Autodesk Inventor part; units mm, degrees
(part 2 of 2)
  spline S54 degree 4 poles (-14.1067, -24.3314) (-14.1229, -24.3628) (-14.1546, -24.4254) (-14.1992, -24.5181) (-14.2532, -24.6396) (-14.3019, -24.7593) (-14.3455, -24.8773) (-14.3847, -24.9943) (-14.4205, -25.111) (-14.4537, -25.2282) (-14.4852, -25.3466) (-14.5154, -25.4664) (-14.5442, -25.5876) (-14.5715, -25.7098) (-14.5972, -25.8326) (-14.621, -25.9559) (-14.6431, -26.0796) (-14.6637, -26.2039) (-14.6827, -26.3288) (-14.7005, -26.4543) (-14.7169, -26.5805) (-14.7319, -26.7073) (-14.7456, -26.8346) (-14.758, -26.9623) (-14.769, -27.0904) (-14.7787, -27.219) (-14.7871, -27.348) (-14.7943, -27.4775) (-14.8002, -27.6074) (-14.8038, -27.7051) (-14.8058, -27.7704) (-14.8066, -27.8031) knots 0 0 0 0 0 0.035714 0.071429 0.107143 0.142857 0.178571 0.214286 0.25 0.285714 0.321429 0.357143 0.392857 0.428571 0.464286 0.5 0.535714 0.571429 0.607143 0.642857 0.678571 0.714286 0.75 0.785714 0.821429 0.857143 0.892857 0.928571 0.964286 1 1 1 1 1
  spline S55 degree 4 poles (-13.7901, -28.3211) (-13.7641, -28.3012) (-13.7125, -28.2612) (-13.6355, -28.2008) (-13.5339, -28.1196) (-13.4334, -28.0377) (-13.334, -27.9551) (-13.2357, -27.8717) (-13.1385, -27.7874) (-13.0424, -27.7024) (-12.9475, -27.6164) (-12.8538, -27.5297) (-12.7614, -27.4423) (-12.6702, -27.3541) (-12.5804, -27.2653) (-12.4919, -27.1757) (-12.4048, -27.0851) (-12.3191, -26.9933) (-12.2348, -26.9004) (-12.152, -26.8064) (-12.071, -26.7119) (-11.9917, -26.617) (-11.9144, -26.522) (-11.8391, -26.4262) (-11.7657, -26.3287) (-11.6941, -26.2282) (-11.6243, -26.1235) (-11.5561, -26.0139) (-11.4895, -25.8987) (-11.4407, -25.8081) (-11.4087, -25.7458) (-11.3928, -25.7142) knots 0 0 0 0 0 0.035714 0.071429 0.107143 0.142857 0.178571 0.214286 0.25 0.285714 0.321429 0.357143 0.392857 0.428571 0.464286 0.5 0.535714 0.571429 0.607143 0.642857 0.678571 0.714286 0.75 0.785714 0.821429 0.857143 0.892857 0.928571 0.964286 1 1 1 1 1
  spline S56 degree 4 poles (-10.1267, -26.2386) (-10.1379, -26.2722) (-10.1593, -26.339) (-10.1888, -26.4376) (-10.2231, -26.5662) (-10.2524, -26.6921) (-10.2771, -26.8155) (-10.2976, -26.9372) (-10.3147, -27.058) (-10.3292, -27.179) (-10.3417, -27.3008) (-10.3528, -27.4239) (-10.3623, -27.5481) (-10.3702, -27.6731) (-10.3763, -27.7984) (-10.3806, -27.9239) (-10.3831, -28.0495) (-10.3839, -28.1755) (-10.3832, -28.3018) (-10.3811, -28.4285) (-10.3775, -28.5557) (-10.3726, -28.6833) (-10.3662, -28.8111) (-10.3584, -28.9392) (-10.3493, -29.0675) (-10.3387, -29.1959) (-10.3269, -29.3247) (-10.3137, -29.4536) (-10.2993, -29.5828) (-10.2875, -29.6799) (-10.2792, -29.7447) (-10.275, -29.7771) knots 0 0 0 0 0 0.035714 0.071429 0.107143 0.142857 0.178571 0.214286 0.25 0.285714 0.321429 0.357143 0.392857 0.428571 0.464286 0.5 0.535714 0.571429 0.607143 0.642857 0.678571 0.714286 0.75 0.785714 0.821429 0.857143 0.892857 0.928571 0.964286 1 1 1 1 1
  spline S57 degree 4 poles (-9.1899, -30.1297) (-9.1674, -30.1059) (-9.1226, -30.0582) (-9.056, -29.9865) (-8.9684, -29.8904) (-8.8819, -29.7937) (-8.7967, -29.6964) (-8.7126, -29.5985) (-8.6298, -29.5001) (-8.5482, -29.4009) (-8.4679, -29.3012) (-8.3889, -29.2008) (-8.3113, -29.0999) (-8.235, -28.9986) (-8.1602, -28.8968) (-8.0869, -28.7944) (-8.015, -28.6913) (-7.9447, -28.5872) (-7.876, -28.4822) (-7.8089, -28.3765) (-7.7436, -28.2705) (-7.6802, -28.1645) (-7.6187, -28.0586) (-7.5593, -27.9523) (-7.502, -27.8446) (-7.4471, -27.7342) (-7.3945, -27.62) (-7.3443, -27.5012) (-7.2965, -27.3771) (-7.2625, -27.2801) (-7.2407, -27.2135) (-7.23, -27.1798) knots 0 0 0 0 0 0.035714 0.071429 0.107143 0.142857 0.178571 0.214286 0.25 0.285714 0.321429 0.357143 0.392857 0.428571 0.464286 0.5 0.535714 0.571429 0.607143 0.642857 0.678571 0.714286 0.75 0.785714 0.821429 0.857143 0.892857 0.928571 0.964286 1 1 1 1 1
  spline S58 degree 4 poles (-5.8974, -27.4997) (-5.9032, -27.5347) (-5.9139, -27.6039) (-5.9277, -27.7059) (-5.9415, -27.8381) (-5.9508, -27.9669) (-5.9558, -28.0927) (-5.957, -28.216) (-5.955, -28.338) (-5.9503, -28.4598) (-5.9437, -28.5821) (-5.9353, -28.7054) (-5.9253, -28.8295) (-5.9135, -28.9542) (-5.9, -29.0789) (-5.8846, -29.2036) (-5.8674, -29.3281) (-5.8485, -29.4526) (-5.828, -29.5772) (-5.8061, -29.7021) (-5.7827, -29.8272) (-5.7579, -29.9524) (-5.7316, -30.0777) (-5.7038, -30.203) (-5.6747, -30.3283) (-5.6442, -30.4536) (-5.6123, -30.5789) (-5.5792, -30.7043) (-5.5447, -30.8297) (-5.5179, -30.9237) (-5.4996, -30.9865) (-5.4903, -31.0178) knots 0 0 0 0 0 0.035714 0.071429 0.107143 0.142857 0.178571 0.214286 0.25 0.285714 0.321429 0.357143 0.392857 0.428571 0.464286 0.5 0.535714 0.571429 0.607143 0.642857 0.678571 0.714286 0.75 0.785714 0.821429 0.857143 0.892857 0.928571 0.964286 1 1 1 1 1
  spline S59 degree 4 poles (-4.3634, -31.1963) (-4.345, -31.1693) (-4.3082, -31.1153) (-4.2537, -31.0341) (-4.1822, -30.9254) (-4.112, -30.8164) (-4.0431, -30.707) (-3.9754, -30.5972) (-3.909, -30.487) (-3.844, -30.3764) (-3.7803, -30.2653) (-3.7181, -30.1538) (-3.6572, -30.0421) (-3.5978, -29.93) (-3.5398, -29.8178) (-3.4834, -29.7052) (-3.4286, -29.5921) (-3.3754, -29.4783) (-3.3239, -29.3639) (-3.2742, -29.249) (-3.2263, -29.134) (-3.1802, -29.0194) (-3.136, -28.9051) (-3.094, -28.7908) (-3.0542, -28.6754) (-3.0172, -28.5578) (-2.983, -28.4367) (-2.9519, -28.3114) (-2.9241, -28.1814) (-2.9057, -28.0803) (-2.8944, -28.0112) (-2.8891, -27.9762) knots 0 0 0 0 0 0.035714 0.071429 0.107143 0.142857 0.178571 0.214286 0.25 0.285714 0.321429 0.357143 0.392857 0.428571 0.464286 0.5 0.535714 0.571429 0.607143 0.642857 0.678571 0.714286 0.75 0.785714 0.821429 0.857143 0.892857 0.928571 0.964286 1 1 1 1 1
  spline S60 degree 4 poles (-1.5229, -28.0837) (-1.5231, -28.1192) (-1.5229, -28.1892) (-1.5205, -28.2922) (-1.5134, -28.4251) (-1.5024, -28.5538) (-1.4877, -28.6788) (-1.4696, -28.8008) (-1.4485, -28.921) (-1.4249, -29.0406) (-1.3992, -29.1603) (-1.3717, -29.2808) (-1.3424, -29.4019) (-1.3113, -29.5231) (-1.2784, -29.6442) (-1.2436, -29.7649) (-1.2072, -29.8852) (-1.169, -30.0052) (-1.1293, -30.1251) (-1.0881, -30.245) (-1.0455, -30.3649) (-1.0014, -30.4847) (-0.9558, -30.6043) (-0.9088, -30.7237) (-0.8604, -30.8429) (-0.8107, -30.9618) (-0.7596, -31.0806) (-0.7073, -31.1991) (-0.6536, -31.3175) (-0.6124, -31.4062) (-0.5845, -31.4653) (-0.5705, -31.4948) knots 0 0 0 0 0 0.035714 0.071429 0.107143 0.142857 0.178571 0.214286 0.25 0.285714 0.321429 0.357143 0.392857 0.428571 0.464286 0.5 0.535714 0.571429 0.607143 0.642857 0.678571 0.714286 0.75 0.785714 0.821429 0.857143 0.892857 0.928571 0.964286 1 1 1 1 1
  spline S61 degree 4 poles (0.5705, -31.4948) (0.5845, -31.4653) (0.6124, -31.4062) (0.6536, -31.3174) (0.7072, -31.1989) (0.7595, -31.0803) (0.8106, -30.9615) (0.8603, -30.8425) (0.9087, -30.7233) (0.9556, -30.6038) (1.0012, -30.4842) (1.0453, -30.3644) (1.0879, -30.2444) (1.1291, -30.1245) (1.1688, -30.0046) (1.2069, -29.8846) (1.2434, -29.7643) (1.2781, -29.6436) (1.3111, -29.5225) (1.3422, -29.4012) (1.3715, -29.2802) (1.3991, -29.1597) (1.4248, -29.04) (1.4484, -28.9205) (1.4696, -28.8003) (1.4877, -28.6783) (1.5025, -28.5534) (1.5135, -28.4248) (1.5206, -28.292) (1.5229, -28.1891) (1.5231, -28.1191) (1.5229, -28.0837) knots 0 0 0 0 0 0.035714 0.071429 0.107143 0.142857 0.178571 0.214286 0.25 0.285714 0.321429 0.357143 0.392857 0.428571 0.464286 0.5 0.535714 0.571429 0.607143 0.642857 0.678571 0.714286 0.75 0.785714 0.821429 0.857143 0.892857 0.928571 0.964286 1 1 1 1 1
  spline S62 degree 4 poles (2.8891, -27.9762) (2.8944, -28.0112) (2.9056, -28.0804) (2.924, -28.1816) (2.9518, -28.3117) (2.9827, -28.4371) (3.0168, -28.5582) (3.0538, -28.676) (3.0935, -28.7914) (3.1355, -28.9058) (3.1796, -29.0201) (3.2257, -29.1348) (3.2736, -29.2498) (3.3233, -29.3647) (3.3747, -29.4792) (3.4279, -29.5929) (3.4827, -29.706) (3.5392, -29.8186) (3.5971, -29.9308) (3.6566, -30.0428) (3.7175, -30.1545) (3.7798, -30.266) (3.8435, -30.377) (3.9086, -30.4876) (3.975, -30.5977) (4.0428, -30.7074) (4.1118, -30.8167) (4.182, -30.9256) (4.2536, -31.0342) (4.3081, -31.1154) (4.3449, -31.1694) (4.3634, -31.1963) knots 0 0 0 0 0 0.035714 0.071429 0.107143 0.142857 0.178571 0.214286 0.25 0.285714 0.321429 0.357143 0.392857 0.428571 0.464286 0.5 0.535714 0.571429 0.607143 0.642857 0.678571 0.714286 0.75 0.785714 0.821429 0.857143 0.892857 0.928571 0.964286 1 1 1 1 1
  spline S63 degree 4 poles (5.4903, -31.0178) (5.4996, -30.9865) (5.5179, -30.9237) (5.5447, -30.8297) (5.5791, -30.7043) (5.6123, -30.579) (5.6441, -30.4537) (5.6746, -30.3284) (5.7038, -30.2031) (5.7315, -30.0778) (5.7577, -29.9525) (5.7826, -29.8273) (5.806, -29.7022) (5.8279, -29.5773) (5.8483, -29.4526) (5.8672, -29.3281) (5.8844, -29.2036) (5.8998, -29.079) (5.9134, -28.9543) (5.9251, -28.8296) (5.9352, -28.7055) (5.9436, -28.5822) (5.9502, -28.4598) (5.9549, -28.3381) (5.9569, -28.216) (5.9558, -28.0926) (5.9508, -27.9669) (5.9415, -27.8381) (5.9277, -27.7058) (5.9139, -27.6039) (5.9032, -27.5347) (5.8974, -27.4997) knots 0 0 0 0 0 0.035714 0.071429 0.107143 0.142857 0.178571 0.214286 0.25 0.285714 0.321429 0.357143 0.392857 0.428571 0.464286 0.5 0.535714 0.571429 0.607143 0.642857 0.678571 0.714286 0.75 0.785714 0.821429 0.857143 0.892857 0.928571 0.964286 1 1 1 1 1
  spline S64 degree 4 poles (7.23, -27.1798) (7.2407, -27.2136) (7.2626, -27.2801) (7.2966, -27.3773) (7.3443, -27.5014) (7.3945, -27.6204) (7.4471, -27.7347) (7.5021, -27.8452) (7.5593, -27.953) (7.6187, -28.0594) (7.6802, -28.1654) (7.7436, -28.2714) (7.8089, -28.3775) (7.876, -28.4832) (7.9447, -28.5882) (8.015, -28.6923) (8.0869, -28.7954) (8.1602, -28.8977) (8.235, -28.9995) (8.3113, -29.1008) (8.3889, -29.2017) (8.4679, -29.302) (8.5482, -29.4017) (8.6298, -29.5007) (8.7126, -29.5991) (8.7967, -29.6969) (8.8819, -29.794) (8.9684, -29.8906) (9.056, -29.9867) (9.1226, -30.0583) (9.1674, -30.1059) (9.1899, -30.1297) knots 0 0 0 0 0 0.035714 0.071429 0.107143 0.142857 0.178571 0.214286 0.25 0.285714 0.321429 0.357143 0.392857 0.428571 0.464286 0.5 0.535714 0.571429 0.607143 0.642857 0.678571 0.714286 0.75 0.785714 0.821429 0.857143 0.892857 0.928571 0.964286 1 1 1 1 1
  spline S65 degree 4 poles (10.275, -29.7771) (10.2792, -29.7446) (10.2874, -29.6798) (10.2992, -29.5826) (10.3135, -29.4533) (10.3266, -29.3243) (10.3384, -29.1955) (10.3489, -29.0669) (10.3581, -28.9386) (10.3658, -28.8104) (10.3721, -28.6825) (10.377, -28.5549) (10.3805, -28.4277) (10.3826, -28.3009) (10.3833, -28.1745) (10.3825, -28.0486) (10.38, -27.9229) (10.3758, -27.7974) (10.3696, -27.6721) (10.3618, -27.5471) (10.3523, -27.423) (10.3413, -27.2999) (10.3288, -27.1781) (10.3144, -27.0572) (10.2973, -26.9364) (10.277, -26.8148) (10.2524, -26.6915) (10.2231, -26.5658) (10.1889, -26.4374) (10.1593, -26.3389) (10.1379, -26.2722) (10.1267, -26.2386) knots 0 0 0 0 0 0.035714 0.071429 0.107143 0.142857 0.178571 0.214286 0.25 0.285714 0.321429 0.357143 0.392857 0.428571 0.464286 0.5 0.535714 0.571429 0.607143 0.642857 0.678571 0.714286 0.75 0.785714 0.821429 0.857143 0.892857 0.928571 0.964286 1 1 1 1 1
  spline S66 degree 4 poles (11.3928, -25.7142) (11.4087, -25.7458) (11.4407, -25.8081) (11.4895, -25.8987) (11.5561, -26.0139) (11.6243, -26.1236) (11.6941, -26.2283) (11.7657, -26.3288) (11.8391, -26.4263) (11.9144, -26.5221) (11.9917, -26.6172) (12.071, -26.712) (12.152, -26.8066) (12.2348, -26.9005) (12.3191, -26.9935) (12.4048, -27.0852) (12.4919, -27.1759) (12.5804, -27.2655) (12.6702, -27.3543) (12.7614, -27.4424) (12.8538, -27.5299) (12.9475, -27.6166) (13.0424, -27.7025) (13.1385, -27.7875) (13.2357, -27.8718) (13.334, -27.9552) (13.4334, -28.0378) (13.5339, -28.1197) (13.6355, -28.2009) (13.7125, -28.2612) (13.7641, -28.3012) (13.7901, -28.3211) knots 0 0 0 0 0 0.035714 0.071429 0.107143 0.142857 0.178571 0.214286 0.25 0.285714 0.321429 0.357143 0.392857 0.428571 0.464286 0.5 0.535714 0.571429 0.607143 0.642857 0.678571 0.714286 0.75 0.785714 0.821429 0.857143 0.892857 0.928571 0.964286 1 1 1 1 1
  spline S67 degree 4 poles (14.8066, -27.8031) (14.8058, -27.7704) (14.8038, -27.7051) (14.8002, -27.6074) (14.7942, -27.4775) (14.7871, -27.348) (14.7786, -27.219) (14.7689, -27.0905) (14.7579, -26.9623) (14.7456, -26.8346) (14.7319, -26.7073) (14.7168, -26.5806) (14.7004, -26.4544) (14.6826, -26.3288) (14.6635, -26.204) (14.643, -26.0797) (14.6209, -25.956) (14.5971, -25.8327) (14.5714, -25.7099) (14.5441, -25.5877) (14.5152, -25.4665) (14.4851, -25.3466) (14.4536, -25.2282) (14.4204, -25.111) (14.3847, -24.9943) (14.3454, -24.8773) (14.3018, -24.7593) (14.2532, -24.6396) (14.1992, -24.5181) (14.1545, -24.4253) (14.1229, -24.3628) (14.1067, -24.3314) knots 0 0 0 0 0 0.035714 0.071429 0.107143 0.142857 0.178571 0.214286 0.25 0.285714 0.321429 0.357143 0.392857 0.428571 0.464286 0.5 0.535714 0.571429 0.607143 0.642857 0.678571 0.714286 0.75 0.785714 0.821429 0.857143 0.892857 0.928571 0.964286 1 1 1 1 1
  spline S68 degree 4 poles (15.2751, -23.6154) (15.2958, -23.6441) (15.3371, -23.7007) (15.3995, -23.7826) (15.4833, -23.8859) (15.5678, -23.9835) (15.6532, -24.076) (15.7396, -24.1641) (15.8273, -24.249) (15.9167, -24.3318) (16.0079, -24.4136) (16.101, -24.4949) (16.1959, -24.5756) (16.2924, -24.6554) (16.3902, -24.734) (16.4892, -24.8113) (16.5894, -24.8871) (16.6908, -24.9618) (16.7934, -25.0355) (16.8972, -25.1083) (17.0022, -25.1802) (17.1083, -25.2512) (17.2155, -25.3212) (17.3236, -25.3901) (17.4328, -25.4581) (17.543, -25.5251) (17.6541, -25.5912) (17.7662, -25.6563) (17.8792, -25.7206) (17.9647, -25.7681) (18.022, -25.7995) (18.0507, -25.8152) knots 0 0 0 0 0 0.035714 0.071429 0.107143 0.142857 0.178571 0.214286 0.25 0.285714 0.321429 0.357143 0.392857 0.428571 0.464286 0.5 0.535714 0.571429 0.607143 0.642857 0.678571 0.714286 0.75 0.785714 0.821429 0.857143 0.892857 0.928571 0.964286 1 1 1 1 1
  spline S69 degree 4 poles (18.9737, -25.1445) (18.9677, -25.1124) (18.9555, -25.0482) (18.9367, -24.9522) (18.9105, -24.8248) (18.8831, -24.6981) (18.8546, -24.572) (18.8249, -24.4465) (18.794, -24.3217) (18.7618, -24.1975) (18.7283, -24.0739) (18.6936, -23.951) (18.6576, -23.829) (18.6205, -23.7077) (18.5821, -23.5874) (18.5424, -23.4679) (18.5012, -23.3491) (18.4584, -23.2311) (18.4138, -23.1138) (18.3677, -22.9974) (18.3203, -22.8822) (18.2718, -22.7685) (18.2222, -22.6565) (18.171, -22.5459) (18.1175, -22.4362) (18.0604, -22.3269) (17.9989, -22.2171) (17.9321, -22.1066) (17.8598, -21.995) (17.8012, -21.9104) (17.7602, -21.8536) (17.7393, -21.8251) knots 0 0 0 0 0 0.035714 0.071429 0.107143 0.142857 0.178571 0.214286 0.25 0.285714 0.321429 0.357143 0.392857 0.428571 0.464286 0.5 0.535714 0.571429 0.607143 0.642857 0.678571 0.714286 0.75 0.785714 0.821429 0.857143 0.892857 0.928571 0.964286 1 1 1 1 1
  spline S70 degree 4 poles (18.7813, -20.9351) (18.8062, -20.9602) (18.8559, -21.0096) (18.9303, -21.0807) (19.0292, -21.1696) (19.1279, -21.2528) (19.2266, -21.3307) (19.3257, -21.4041) (19.4256, -21.4741) (19.5268, -21.5419) (19.6297, -21.6084) (19.7343, -21.674) (19.8407, -21.7389) (19.9484, -21.8026) (20.0573, -21.865) (20.1672, -21.9258) (20.278, -21.985) (20.3899, -22.0429) (20.5027, -22.0997) (20.6167, -22.1554) (20.7316, -22.21) (20.8476, -22.2635) (20.9644, -22.3159) (21.0821, -22.3672) (21.2006, -22.4173) (21.3199, -22.4663) (21.44, -22.5142) (21.5609, -22.5611) (21.6826, -22.6069) (21.7745, -22.6406) (21.836, -22.6626) (21.8668, -22.6736) knots 0 0 0 0 0 0.035714 0.071429 0.107143 0.142857 0.178571 0.214286 0.25 0.285714 0.321429 0.357143 0.392857 0.428571 0.464286 0.5 0.535714 0.571429 0.607143 0.642857 0.678571 0.714286 0.75 0.785714 0.821429 0.857143 0.892857 0.928571 0.964286 1 1 1 1 1
  spline S71 degree 4 poles (22.6736, -21.8668) (22.6626, -21.836) (22.6406, -21.7745) (22.607, -21.6827) (22.5612, -21.561) (22.5143, -21.4401) (22.4665, -21.32) (22.4175, -21.2007) (22.3674, -21.0823) (22.3162, -20.9646) (22.2638, -20.8478) (22.2103, -20.7319) (22.1557, -20.617) (22.1001, -20.5031) (22.0433, -20.3902) (21.9854, -20.2784) (21.9262, -20.1675) (21.8654, -20.0576) (21.803, -19.9487) (21.7393, -19.841) (21.6744, -19.7347) (21.6087, -19.63) (21.5422, -19.5271) (21.4743, -19.4258) (21.4043, -19.3259) (21.3308, -19.2268) (21.2528, -19.128) (21.1696, -19.0292) (21.0807, -18.9303) (21.0096, -18.8559) (20.9602, -18.8062) (20.9351, -18.7813) knots 0 0 0 0 0 0.035714 0.071429 0.107143 0.142857 0.178571 0.214286 0.25 0.285714 0.321429 0.357143 0.392857 0.428571 0.464286 0.5 0.535714 0.571429 0.607143 0.642857 0.678571 0.714286 0.75 0.785714 0.821429 0.857143 0.892857 0.928571 0.964286 1 1 1 1 1
  spline S72 degree 4 poles (21.8251, -17.7393) (21.8536, -17.7602) (21.9104, -17.8012) (21.995, -17.8598) (22.1066, -17.9322) (22.2172, -17.9989) (22.327, -18.0605) (22.4364, -18.1175) (22.546, -18.1711) (22.6567, -18.2223) (22.7687, -18.2719) (22.8824, -18.3204) (22.9975, -18.3679) (23.1139, -18.414) (23.2312, -18.4586) (23.3493, -18.5014) (23.468, -18.5426) (23.5875, -18.5823) (23.7079, -18.6206) (23.8291, -18.6578) (23.9512, -18.6938) (24.074, -18.7285) (24.1976, -18.7619) (24.3218, -18.7941) (24.4466, -18.825) (24.5721, -18.8547) (24.6982, -18.8832) (24.8249, -18.9105) (24.9522, -18.9368) (25.0482, -18.9556) (25.1124, -18.9677) (25.1445, -18.9737) knots 0 0 0 0 0 0.035714 0.071429 0.107143 0.142857 0.178571 0.214286 0.25 0.285714 0.321429 0.357143 0.392857 0.428571 0.464286 0.5 0.535714 0.571429 0.607143 0.642857 0.678571 0.714286 0.75 0.785714 0.821429 0.857143 0.892857 0.928571 0.964286 1 1 1 1 1
  spline S73 degree 4 poles (25.8152, -18.0507) (25.7995, -18.022) (25.7681, -17.9647) (25.7206, -17.8792) (25.6563, -17.7662) (25.5911, -17.6541) (25.525, -17.543) (25.458, -17.4328) (25.39, -17.3236) (25.321, -17.2155) (25.251, -17.1083) (25.18, -17.0022) (25.1081, -16.8972) (25.0353, -16.7934) (24.9616, -16.6908) (24.8869, -16.5894) (24.8111, -16.4892) (24.7338, -16.3902) (24.6552, -16.2923) (24.5754, -16.1959) (24.4947, -16.101) (24.4134, -16.0079) (24.3316, -15.9167) (24.2488, -15.8273) (24.164, -15.7395) (24.0759, -15.6531) (23.9834, -15.5678) (23.8858, -15.4833) (23.7825, -15.3995) (23.7007, -15.3371) (23.6441, -15.2958) (23.6154, -15.2751) knots 0 0 0 0 0 0.035714 0.071429 0.107143 0.142857 0.178571 0.214286 0.25 0.285714 0.321429 0.357143 0.392857 0.428571 0.464286 0.5 0.535714 0.571429 0.607143 0.642857 0.678571 0.714286 0.75 0.785714 0.821429 0.857143 0.892857 0.928571 0.964286 1 1 1 1 1
  spline S74 degree 4 poles (24.3314, -14.1067) (24.3628, -14.1229) (24.4253, -14.1545) (24.5181, -14.1991) (24.6396, -14.2531) (24.7593, -14.3017) (24.8773, -14.3454) (24.9943, -14.3846) (25.111, -14.4203) (25.2282, -14.4536) (25.3466, -14.485) (25.4665, -14.5152) (25.5877, -14.544) (25.7098, -14.5713) (25.8327, -14.597) (25.956, -14.6208) (26.0797, -14.6429) (26.2039, -14.6635) (26.3288, -14.6825) (26.4543, -14.7003) (26.5805, -14.7167) (26.7073, -14.7318) (26.8346, -14.7455) (26.9623, -14.7579) (27.0905, -14.7689) (27.219, -14.7786) (27.348, -14.787) (27.4775, -14.7942) (27.6074, -14.8002) (27.7051, -14.8038) (27.7704, -14.8058) (27.8031, -14.8066) knots 0 0 0 0 0 0.035714 0.071429 0.107143 0.142857 0.178571 0.214286 0.25 0.285714 0.321429 0.357143 0.392857 0.428571 0.464286 0.5 0.535714 0.571429 0.607143 0.642857 0.678571 0.714286 0.75 0.785714 0.821429 0.857143 0.892857 0.928571 0.964286 1 1 1 1 1
  spline S75 degree 4 poles (28.3211, -13.7901) (28.3012, -13.7641) (28.2612, -13.7125) (28.2008, -13.6355) (28.1196, -13.5339) (28.0377, -13.4334) (27.955, -13.334) (27.8716, -13.2357) (27.7874, -13.1385) (27.7023, -13.0424) (27.6164, -12.9475) (27.5296, -12.8538) (27.4422, -12.7613) (27.354, -12.6702) (27.2652, -12.5804) (27.1756, -12.4919) (27.085, -12.4048) (26.9932, -12.3191) (26.9003, -12.2348) (26.8063, -12.152) (26.7118, -12.0709) (26.617, -11.9917) (26.5219, -11.9144) (26.4261, -11.8391) (26.3286, -11.7657) (26.2281, -11.6941) (26.1235, -11.6243) (26.0138, -11.5561) (25.8987, -11.4895) (25.8081, -11.4407) (25.7458, -11.4087) (25.7142, -11.3928) knots 0 0 0 0 0 0.035714 0.071429 0.107143 0.142857 0.178571 0.214286 0.25 0.285714 0.321429 0.357143 0.392857 0.428571 0.464286 0.5 0.535714 0.571429 0.607143 0.642857 0.678571 0.714286 0.75 0.785714 0.821429 0.857143 0.892857 0.928571 0.964286 1 1 1 1 1
  spline S76 degree 4 poles (26.2386, -10.1267) (26.2722, -10.1379) (26.3389, -10.1593) (26.4375, -10.1889) (26.566, -10.2232) (26.6918, -10.2525) (26.8152, -10.2771) (26.9369, -10.2976) (27.0578, -10.3147) (27.1788, -10.3292) (27.3006, -10.3417) (27.4237, -10.3528) (27.5479, -10.3623) (27.6729, -10.3702) (27.7982, -10.3763) (27.9237, -10.3806) (28.0494, -10.3831) (28.1753, -10.3839) (28.3016, -10.3832) (28.4284, -10.3811) (28.5556, -10.3775) (28.6832, -10.3726) (28.811, -10.3662) (28.9391, -10.3584) (29.0674, -10.3493) (29.1959, -10.3387) (29.3246, -10.3268) (29.4536, -10.3137) (29.5828, -10.2993) (29.6798, -10.2875) (29.7447, -10.2792) (29.7771, -10.275) knots 0 0 0 0 0 0.035714 0.071429 0.107143 0.142857 0.178571 0.214286 0.25 0.285714 0.321429 0.357143 0.392857 0.428571 0.464286 0.5 0.535714 0.571429 0.607143 0.642857 0.678571 0.714286 0.75 0.785714 0.821429 0.857143 0.892857 0.928571 0.964286 1 1 1 1 1
  spline S77 degree 4 poles (30.1297, -9.1899) (30.1059, -9.1674) (30.0583, -9.1226) (29.9867, -9.056) (29.8906, -8.9684) (29.794, -8.882) (29.6968, -8.7968) (29.5991, -8.7127) (29.5007, -8.6299) (29.4016, -8.5483) (29.3019, -8.4681) (29.2016, -8.3891) (29.1008, -8.3115) (28.9995, -8.2353) (28.8977, -8.1604) (28.7953, -8.0871) (28.6922, -8.0152) (28.5881, -7.9449) (28.4832, -7.8762) (28.3774, -7.8092) (28.2713, -7.7439) (28.1653, -7.6804) (28.0593, -7.6189) (27.9529, -7.5595) (27.8451, -7.5022) (27.7346, -7.4473) (27.6203, -7.3946) (27.5013, -7.3444) (27.3772, -7.2966) (27.2801, -7.2626) (27.2135, -7.2407) (27.1798, -7.23) knots 0 0 0 0 0 0.035714 0.071429 0.107143 0.142857 0.178571 0.214286 0.25 0.285714 0.321429 0.357143 0.392857 0.428571 0.464286 0.5 0.535714 0.571429 0.607143 0.642857 0.678571 0.714286 0.75 0.785714 0.821429 0.857143 0.892857 0.928571 0.964286 1 1 1 1 1
  spline S78 degree 4 poles (27.4997, -5.8974) (27.5347, -5.9032) (27.6039, -5.9139) (27.7059, -5.9277) (27.8382, -5.9415) (27.967, -5.9508) (28.0928, -5.9558) (28.2161, -5.957) (28.3382, -5.955) (28.46, -5.9504) (28.5823, -5.9437) (28.7056, -5.9353) (28.8298, -5.9253) (28.9544, -5.9136) (29.0792, -5.9) (29.2038, -5.8846) (29.3283, -5.8674) (29.4528, -5.8485) (29.5775, -5.828) (29.7023, -5.8061) (29.8274, -5.7827) (29.9527, -5.7579) (30.0779, -5.7316) (30.2032, -5.7039) (30.3285, -5.6747) (30.4537, -5.6442) (30.579, -5.6124) (30.7043, -5.5792) (30.8297, -5.5447) (30.9238, -5.5179) (30.9865, -5.4996) (31.0178, -5.4903) knots 0 0 0 0 0 0.035714 0.071429 0.107143 0.142857 0.178571 0.214286 0.25 0.285714 0.321429 0.357143 0.392857 0.428571 0.464286 0.5 0.535714 0.571429 0.607143 0.642857 0.678571 0.714286 0.75 0.785714 0.821429 0.857143 0.892857 0.928571 0.964286 1 1 1 1 1
  spline S79 degree 4 poles (31.1963, -4.3634) (31.1694, -4.3449) (31.1153, -4.3081) (31.0342, -4.2536) (30.9256, -4.1821) (30.8166, -4.1118) (30.7073, -4.0428) (30.5976, -3.9751) (30.4874, -3.9087) (30.3769, -3.8436) (30.2658, -3.7799) (30.1544, -3.7176) (30.0427, -3.6567) (29.9307, -3.5973) (29.8184, -3.5393) (29.7059, -3.4829) (29.5928, -3.428) (29.479, -3.3749) (29.3645, -3.3234) (29.2496, -3.2737) (29.1346, -3.2258) (29.02, -3.1797) (28.9057, -3.1356) (28.7913, -3.0936) (28.6759, -3.0539) (28.5582, -3.0169) (28.437, -2.9828) (28.3117, -2.9518) (28.1816, -2.924) (28.0803, -2.9056) (28.0112, -2.8944) (27.9762, -2.8891) knots 0 0 0 0 0 0.035714 0.071429 0.107143 0.142857 0.178571 0.214286 0.25 0.285714 0.321429 0.357143 0.392857 0.428571 0.464286 0.5 0.535714 0.571429 0.607143 0.642857 0.678571 0.714286 0.75 0.785714 0.821429 0.857143 0.892857 0.928571 0.964286 1 1 1 1 1
  arc A0 (31.4948, -0.5705) -> (31.4948, 0.5705) centre (0, 0) ccw
  arc A1 (28.0837, 1.5229) -> (27.9762, 2.8891) centre (0, 0) ccw
  arc A2 (31.1963, 4.3634) -> (31.0178, 5.4903) centre (0, 0) ccw
  arc A3 (27.4997, 5.8974) -> (27.1798, 7.23) centre (0, 0) ccw
  arc A4 (30.1297, 9.1899) -> (29.7771, 10.275) centre (0, 0) ccw
  arc A5 (26.2386, 10.1267) -> (25.7142, 11.3928) centre (0, 0) ccw
  arc A6 (28.3211, 13.7901) -> (27.8031, 14.8066) centre (0, 0) ccw
  arc A7 (24.3314, 14.1067) -> (23.6154, 15.2751) centre (0, 0) ccw
  arc A8 (25.8152, 18.0507) -> (25.1445, 18.9737) centre (0, 0) ccw
  arc A9 (21.8251, 17.7393) -> (20.9351, 18.7813) centre (0, 0) ccw
  arc A10 (22.6736, 21.8668) -> (21.8668, 22.6736) centre (0, 0) ccw
  arc A11 (18.7813, 20.9351) -> (17.7393, 21.8251) centre (0, 0) ccw
  arc A12 (18.9737, 25.1445) -> (18.0507, 25.8152) centre (0, 0) ccw
  arc A13 (15.2751, 23.6154) -> (14.1067, 24.3314) centre (0, 0) ccw
  arc A14 (14.8066, 27.8031) -> (13.7901, 28.3211) centre (0, 0) ccw
  arc A15 (11.3928, 25.7142) -> (10.1267, 26.2386) centre (0, 0) ccw
  arc A16 (10.275, 29.7771) -> (9.1899, 30.1297) centre (0, 0) ccw
  arc A17 (7.23, 27.1798) -> (5.8974, 27.4997) centre (0, 0) ccw
  arc A18 (5.4903, 31.0178) -> (4.3634, 31.1963) centre (0, 0) ccw
  arc A19 (2.8891, 27.9762) -> (1.5229, 28.0837) centre (0, 0) ccw
  arc A20 (0.5705, 31.4948) -> (-0.5705, 31.4948) centre (0, 0) ccw
  arc A21 (-1.5229, 28.0837) -> (-2.8891, 27.9762) centre (0, 0) ccw
  arc A22 (-4.3634, 31.1963) -> (-5.4903, 31.0178) centre (0, 0) ccw
  arc A23 (-5.8974, 27.4997) -> (-7.23, 27.1798) centre (0, 0) ccw
  arc A24 (-9.1899, 30.1297) -> (-10.275, 29.7771) centre (0, 0) ccw
  arc A25 (-10.1267, 26.2386) -> (-11.3928, 25.7142) centre (0, 0) ccw
  arc A26 (-13.7901, 28.3211) -> (-14.8066, 27.8031) centre (0, 0) ccw
  arc A27 (-14.1067, 24.3314) -> (-15.2751, 23.6154) centre (0, 0) ccw
  arc A28 (-18.0507, 25.8152) -> (-18.9737, 25.1445) centre (0, 0) ccw
  arc A29 (-17.7393, 21.8251) -> (-18.7813, 20.9351) centre (0, 0) ccw
  arc A30 (-21.8668, 22.6736) -> (-22.6736, 21.8668) centre (0, 0) ccw
  arc A31 (-20.9351, 18.7813) -> (-21.8251, 17.7393) centre (0, 0) ccw
  arc A32 (-25.1445, 18.9737) -> (-25.8152, 18.0507) centre (0, 0) ccw
  arc A33 (-23.6154, 15.2751) -> (-24.3314, 14.1067) centre (0, 0) ccw
  arc A34 (-27.8031, 14.8066) -> (-28.3211, 13.7901) centre (0, 0) ccw
  arc A35 (-25.7142, 11.3928) -> (-26.2386, 10.1267) centre (0, 0) ccw
  arc A36 (-29.7771, 10.275) -> (-30.1297, 9.1899) centre (0, 0) ccw
  arc A37 (-27.1798, 7.23) -> (-27.4997, 5.8974) centre (0, 0) ccw
  arc A38 (-31.0178, 5.4903) -> (-31.1963, 4.3634) centre (0, 0) ccw
  arc A39 (-27.9762, 2.8891) -> (-28.0837, 1.5229) centre (0, 0) ccw
  arc A40 (-31.4948, 0.5705) -> (-31.4948, -0.5705) centre (0, 0) ccw
  arc A41 (-28.0837, -1.5229) -> (-27.9762, -2.8891) centre (0, 0) ccw
  arc A42 (-31.1963, -4.3634) -> (-31.0178, -5.4903) centre (0, 0) ccw
  arc A43 (-27.4997, -5.8974) -> (-27.1798, -7.23) centre (0, 0) ccw
  arc A44 (-30.1297, -9.1899) -> (-29.7771, -10.275) centre (0, 0) ccw
  arc A45 (-26.2386, -10.1267) -> (-25.7142, -11.3928) centre (0, 0) ccw
  arc A46 (-28.3211, -13.7901) -> (-27.8031, -14.8066) centre (0, 0) ccw
  arc A47 (-24.3314, -14.1067) -> (-23.6154, -15.2751) centre (0, 0) ccw
  arc A48 (-25.8152, -18.0507) -> (-25.1445, -18.9737) centre (0, 0) ccw
  arc A49 (-21.8251, -17.7393) -> (-20.9351, -18.7813) centre (0, 0) ccw
  arc A50 (-22.6736, -21.8668) -> (-21.8668, -22.6736) centre (0, 0) ccw
  arc A51 (-18.7813, -20.9351) -> (-17.7393, -21.8251) centre (0, 0) ccw
  arc A52 (-18.9737, -25.1445) -> (-18.0507, -25.8152) centre (0, 0) ccw
  arc A53 (-15.2751, -23.6154) -> (-14.1067, -24.3314) centre (0, 0) ccw
  arc A54 (-14.8066, -27.8031) -> (-13.7901, -28.3211) centre (0, 0) ccw
  arc A55 (-11.3928, -25.7142) -> (-10.1267, -26.2386) centre (0, 0) ccw
  arc A56 (-10.275, -29.7771) -> (-9.1899, -30.1297) centre (0, 0) ccw
  arc A57 (-7.23, -27.1798) -> (-5.8974, -27.4997) centre (0, 0) ccw
  arc A58 (-5.4903, -31.0178) -> (-4.3634, -31.1963) centre (0, 0) ccw
  arc A59 (-2.8891, -27.9762) -> (-1.5229, -28.0837) centre (0, 0) ccw
  arc A60 (-0.5705, -31.4948) -> (0.5705, -31.4948) centre (0, 0) ccw
  arc A61 (1.5229, -28.0837) -> (2.8891, -27.9762) centre (0, 0) ccw
  arc A62 (4.3634, -31.1963) -> (5.4903, -31.0178) centre (0, 0) ccw
  arc A63 (5.8974, -27.4997) -> (7.23, -27.1798) centre (0, 0) ccw
  arc A64 (9.1899, -30.1297) -> (10.275, -29.7771) centre (0, 0) ccw
  arc A65 (10.1267, -26.2386) -> (11.3928, -25.7142) centre (0, 0) ccw
  arc A66 (13.7901, -28.3211) -> (14.8066, -27.8031) centre (0, 0) ccw
  arc A67 (14.1067, -24.3314) -> (15.2751, -23.6154) centre (0, 0) ccw
  arc A68 (18.0507, -25.8152) -> (18.9737, -25.1445) centre (0, 0) ccw
  arc A69 (17.7393, -21.8251) -> (18.7813, -20.9351) centre (0, 0) ccw
  arc A70 (21.8668, -22.6736) -> (22.6736, -21.8668) centre (0, 0) ccw
  arc A71 (20.9351, -18.7813) -> (21.8251, -17.7393) centre (0, 0) ccw
  arc A72 (25.1445, -18.9737) -> (25.8152, -18.0507) centre (0, 0) ccw
  arc A73 (23.6154, -15.2751) -> (24.3314, -14.1067) centre (0, 0) ccw
  arc A74 (27.8031, -14.8066) -> (28.3211, -13.7901) centre (0, 0) ccw
  arc A75 (25.7142, -11.3928) -> (26.2386, -10.1267) centre (0, 0) ccw
  arc A76 (29.7771, -10.275) -> (30.1297, -9.1899) centre (0, 0) ccw
  arc A77 (27.1798, -7.23) -> (27.4997, -5.8974) centre (0, 0) ccw
  arc A78 (31.0178, -5.4903) -> (31.1963, -4.3634) centre (0, 0) ccw
  arc A79 (27.9762, -2.8891) -> (28.0837, -1.5229) centre (0, 0) ccw
  point P0 (28.6277, -1.4881)
  point P1 (29.1053, -1.4048)
  point P2 (29.5839, -1.2884)
  point P3 (30.0627, -1.1443)
  point P4 (30.5411, -0.9754)
  point P5 (31.0187, -0.7836)
  point P6 (31.0173, 0.7863)
  point P7 (30.5388, 0.9798)
  point P8 (30.0598, 1.1499)
  point P9 (29.5807, 1.2944)
  point P10 (29.1022, 1.4106)
  point P11 (28.6248, 1.4931)
  point P12 (28.5051, 3.0036)
  point P13 (28.9634, 3.1601)
  point P14 (29.4178, 3.3498)
  point P15 (29.8684, 3.5675)
  point P16 (30.3152, 3.8102)
  point P17 (30.7579, 4.076)
  point P18 (30.5124, 5.6289)
  point P19 (30.0095, 5.7453)
  point P20 (29.5098, 5.8383)
  point P21 (29.014, 5.9062)
  point P22 (28.5231, 5.9461)
  point P23 (28.0387, 5.9528)
  point P24 (27.6847, 7.4254)
  point P25 (28.113, 7.6515)
  point P26 (28.5321, 7.9099)
  point P27 (28.9431, 8.1955)
  point P28 (29.3463, 8.5052)
  point P29 (29.7418, 8.8371)
  point P30 (29.2564, 10.3327)
  point P31 (28.7416, 10.369)
  point P32 (28.2336, 10.3827)
  point P33 (27.7333, 10.3722)
  point P34 (27.2423, 10.3348)
  point P35 (26.7629, 10.2656)
  point P36 (26.1821, 11.665)
  point P37 (26.5697, 11.9555)
  point P38 (26.9433, 12.2763)
  point P39 (27.3046, 12.6226)
  point P40 (27.6544, 12.9915)
  point P41 (27.9932, 13.3811)
  point P42 (27.2797, 14.7822)
  point P43 (26.7655, 14.7375)
  point P44 (26.2615, 14.6715)
  point P45 (25.769, 14.5828)
  point P46 (25.2898, 14.4691)
  point P47 (24.8269, 14.3258)
  point P48 (24.0353, 15.617)
  point P49 (24.3729, 15.9644)
  point P50 (24.6918, 16.3397)
  point P51 (24.9944, 16.7383)
  point P52 (25.2821, 17.1574)
  point P53 (25.5555, 17.5953)
  point P54 (24.6317, 18.8675)
  point P55 (24.131, 18.7427)
  point P56 (23.6436, 18.5986)
  point P57 (23.1711, 18.434)
  point P58 (22.7156, 18.2467)
  point P59 (22.2807, 18.0329)
  point P60 (21.2956, 19.1847)
  point P61 (21.5743, 19.5807)
  point P62 (21.8303, 20.0013)
  point P63 (22.067, 20.4423)
  point P64 (22.2858, 20.9013)
  point P65 (22.4878, 21.3765)
  point P66 (21.3765, 22.4886)
  point P67 (20.9012, 22.2872)
  point P68 (20.4422, 22.0687)
  point P69 (20.0012, 21.8322)
  point P70 (19.5806, 21.5759)
  point P71 (19.1847, 21.2966)
  point P72 (18.0328, 22.2801)
  point P73 (18.2465, 22.7149)
  point P74 (18.4337, 23.1704)
  point P75 (18.5984, 23.643)
  point P76 (18.7425, 24.1305)
  point P77 (18.8674, 24.6314)
  point P78 (17.5955, 25.5557)
  point P79 (17.1576, 25.2825)
  point P80 (16.7385, 24.9949)
  point P81 (16.34, 24.6923)
  point P82 (15.9646, 24.3734)
  point P83 (15.6172, 24.0356)
  point P84 (14.3258, 24.8266)
  point P85 (14.4691, 25.2894)
  point P86 (14.5828, 25.7685)
  point P87 (14.6715, 26.2611)
  point P88 (14.7375, 26.7651)
  point P89 (14.7822, 27.2795)
  point P90 (13.3811, 27.9936)
  point P91 (12.9915, 27.6552)
  point P92 (12.6226, 27.3057)
  point P93 (12.2763, 26.9444)
  point P94 (11.9554, 26.5707)
  point P95 (11.6651, 26.1827)
  point P96 (10.2657, 26.7621)
  point P97 (10.3347, 27.2416)
  point P98 (10.3721, 27.7327)
  point P99 (10.3827, 28.233)
  point P100 (10.369, 28.7412)
  point P101 (10.3327, 29.2561)
  point P102 (8.8368, 29.7422)
  point P103 (8.5046, 29.347)
  point P104 (8.1948, 28.944)
  point P105 (7.9092, 28.5331)
  point P106 (7.6508, 28.1138)
  point P107 (7.425, 27.6852)
  point P108 (5.9529, 28.0385)
  point P109 (5.9461, 28.5229)
  point P110 (5.9062, 29.0138)
  point P111 (5.8383, 29.5096)
  point P112 (5.7453, 30.0094)
  point P113 (5.6289, 30.5123)
  point P114 (4.0754, 30.7585)
  point P115 (3.8092, 30.3162)
  point P116 (3.5662, 29.8697)
  point P117 (3.3484, 29.4191)
  point P118 (3.1588, 28.9646)
  point P119 (3.0028, 28.5059)
  point P120 (1.4937, 28.6245)
  point P121 (1.4114, 29.102)
  point P122 (1.2952, 29.5806)
  point P123 (1.1506, 30.0597)
  point P124 (0.9804, 30.5387)
  point P125 (0.7866, 31.0172)
  point P126 (-0.7866, 31.0173)
  point P127 (-0.9805, 30.5388)
  point P128 (-1.1506, 30.0597)
  point P129 (-1.2953, 29.5807)
  point P130 (-1.4114, 29.1021)
  point P131 (-1.4937, 28.6246)
  point P132 (-3.0025, 28.5058)
  point P133 (-3.1585, 28.9645)
  point P134 (-3.3481, 29.419)
  point P135 (-3.5659, 29.8695)
  point P136 (-3.8089, 30.3161)
  point P137 (-4.0752, 30.7584)
  point P138 (-5.629, 30.5123)
  point P139 (-5.7456, 30.0094)
  point P140 (-5.8387, 29.5096)
  point P141 (-5.9066, 29.0138)
  point P142 (-5.9465, 28.523)
  point P143 (-5.9531, 28.0385)
  point P144 (-7.4248, 27.6851)
  point P145 (-7.6507, 28.1137)
  point P146 (-7.909, 28.533)
  point P147 (-8.1946, 28.944)
  point P148 (-8.5045, 29.347)
  point P149 (-8.8367, 29.7422)
  point P150 (-10.333, 29.2561)
  point P151 (-10.3696, 28.7411)
  point P152 (-10.3834, 28.2329)
  point P153 (-10.3729, 27.7326)
  point P154 (-10.3355, 27.2415)
  point P155 (-10.2662, 26.762)
  point P156 (-11.6643, 26.1828)
  point P157 (-11.9543, 26.5708)
  point P158 (-12.2751, 26.9445)
  point P159 (-12.6215, 27.3057)
  point P160 (-12.9906, 27.6553)
  point P161 (-13.3806, 27.9937)
  point P162 (-14.7825, 27.2794)
  point P163 (-14.7381, 26.7651)
  point P164 (-14.6723, 26.261)
  point P165 (-14.5836, 25.7684)
  point P166 (-14.4698, 25.2893)
  point P167 (-14.3263, 24.8265)
  point P168 (-15.6165, 24.0357)
  point P169 (-15.9638, 24.3736)
  point P170 (-16.339, 24.6925)
  point P171 (-16.7376, 24.9951)
  point P172 (-17.1569, 25.2826)
  point P173 (-17.595, 25.5559)
  point P174 (-18.868, 24.6311)
  point P175 (-18.7436, 24.13)
  point P176 (-18.5997, 23.6424)
  point P177 (-18.4352, 23.1698)
  point P178 (-18.2478, 22.7144)
  point P179 (-18.0337, 22.2798)
  point P180 (-19.1843, 21.2969)
  point P181 (-19.5801, 21.5763)
  point P182 (-20.0007, 21.8326)
  point P183 (-20.4417, 22.069)
  point P184 (-20.9008, 22.2874)
  point P185 (-21.3762, 22.4887)
  point P186 (-22.4888, 21.3763)
  point P187 (-22.2876, 20.9009)
  point P188 (-22.0692, 20.4418)
  point P189 (-21.8327, 20.0008)
  point P190 (-21.5764, 19.5802)
  point P191 (-21.2969, 19.1844)
  point P192 (-22.2797, 18.0335)
  point P193 (-22.7143, 18.2474)
  point P194 (-23.1698, 18.4348)
  point P195 (-23.6424, 18.5994)
  point P196 (-24.13, 18.7433)
  point P197 (-24.6311, 18.8678)
  point P198 (-25.5559, 17.5951)
  point P199 (-25.2828, 17.157)
  constraints: 160 point on circle, 80 centre point, 640 other
extrude "Extrusão2" add sketch "Esboço2" along normal blind 15
sketch "Esboço3" plane through (0, 0, 0) normal (0, 0, 1) x (1, 0, 0)
  circle A0 centre (0, 0) radius 7.5
  dimension "d6" = 15
  constraints: 1 centre point
  measures "d6" diameter of A0
extrude "Extrusão3" cut sketch "Esboço3" along normal through all
equation "\"d0\" = diam_cubo"
equation "\"d1\" = esp_cubo"
equation "\"d4\" = larg_dentada"
equation "\"d6\" = furo"
equation "\"furo\" = 15"
equation "\"diam_cubo\" = 25"
equation "\"esp_cubo\" = 20"
equation "\"larg_dentada\" = 15"
equation "\"folga_dentes\" = 2.5"
equation "\"d3\" = folga_dentes"
